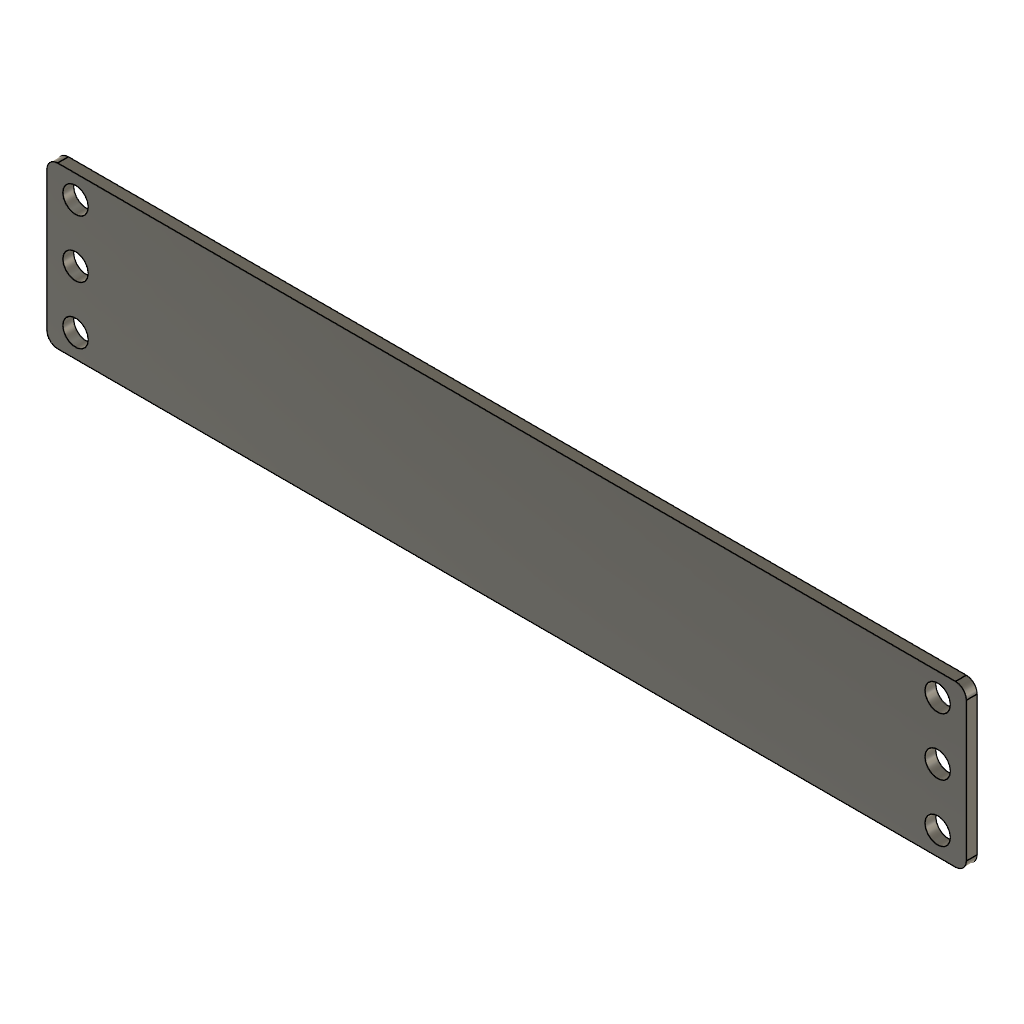
Fusion 360 File - Generic 10inch 1U Template (Autodesk Fusion 360 design; units mm, degrees)
Autodesk Fusion 360 part; units mm, degrees
sketch "Sketch1" plane through (0, 0, 0) normal (0, 1, 0) x (1, 0, 0)
  line L0 (127, 22.225) -> (-127, 22.225)
  line L1 (-127, 22.225) -> (-127, -22.225)
  line L2 (-127, -22.225) -> (127, -22.225)
  line L3 (127, -22.225) -> (127, 22.225)
  line L4 (127, 22.225) -> (-127, -22.225) construction
  line L5 (-127, 22.225) -> (127, -22.225) construction
  circle A0 centre (-119.06, 0) radius 3.5
  circle A1 centre (-119.06, -15.875) radius 3.5
  circle A2 centre (-119.06, 15.875) radius 3.5
  line L6 (0, 22.225) -> (0, -22.225) construction
  circle A3 centre (119.06, 15.875) radius 3.5
  circle A4 centre (119.06, 0) radius 3.5
  circle A5 centre (119.06, -15.875) radius 3.5
  dimension "d1" = 254
  dimension "d2" = 44.45
  dimension "d3" = 7
  dimension "d4" = 7
  dimension "d5" = 7
  dimension "d6" = 7.94
  dimension "d7" = 15.875
  dimension "d8" = 15.875
  constraint horizontal L0
  constraint perpendicular L0 L1
  constraint parallel L0 L2
  constraint parallel L1 L3
  constraint coincident L4 origin
  constraint coincident L5 origin
  constraint vertical A0.centre A1.centre
  constraint vertical A0.centre A2.centre
  constraint midpoint L0 L6.start
  constraint midpoint L2 L6.end
  constraint symmetric A0 L6 A4
  constraint symmetric A1 L6 A5
  constraint symmetric A2 L6 A3
  measures "d1" distance of L1.end L2.end
  measures "d2" distance of L0.end L1.end
  measures "d3" diameter of A0
  measures "d4" diameter of A1
  measures "d5" diameter of A2
  measures "d6" distance of L1 A0.centre
  measures "d7" distance of A0.centre A2.centre
  measures "d8" distance of A0.centre A1.centre
extrude "Extrude1" add sketch "Sketch1" along normal blind 3
fillet "Fillet1" radius 3 4 edges at (-127, 1.5, 22.225) (-127, 1.5, -22.225) (127, 1.5, 22.225) (127, 1.5, -22.225)
